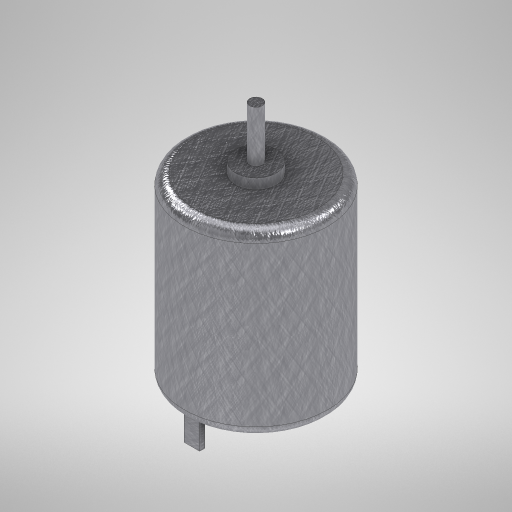
# Autodesk Inventor part: MOTOR
Saved by Autodesk Inventor 2023 (Build 270158000, 158)
## iProperties
Created: 2023-03-29
Part Number: MOTOR
Material: Genérico
Document SubType Name: Modeling
Designer: brand
Density: 1 g/cm^3
Appearance: Valor por defecto
Author: brand
Autodesk Inventor part; units mm, degrees
ref_plane "YZ Plane" through (0, 0, 0) normal (1, 0, 0) x (0, 1, 0)
ref_plane "XZ Plane" through (0, 0, 0) normal (0, 1, 0) x (-1, 0, 0)
ref_plane "XY Plane" through (0, 0, 0) normal (0, 0, 1) x (1, 0, 0)
sketch "Boceto1" plane through (0, 0, 0) normal (0, 1, 0) x (-1, 0, 0)
  circle A0 centre (0, 0) radius 14
  dimension "d0" = 28
  constraints: 1 centre point, 1 coincident
  measures "d0" diameter of A0
extrude "Extrusión1" add sketch "Boceto1" along normal blind 35
sketch "Boceto2" plane through (0, 0, 0) normal (0, -1, 0) x (1, 0, 0)
  line L0 (1.5, 12.5) -> (-1.5, 12.5)
  line L1 (-1.5, 12.5) -> (-1.5, 11.5)
  line L2 (-1.5, 11.5) -> (1.5, 11.5)
  line L3 (1.5, 11.5) -> (1.5, 12.5)
  line L4 (0, 0) -> (4.1398, 0)
  line L5 (1.5, -12.5) -> (-1.5, -12.5)
  line L6 (-1.5, -12.5) -> (-1.5, -11.5)
  line L7 (-1.5, -11.5) -> (1.5, -11.5)
  line L8 (1.5, -11.5) -> (1.5, -12.5)
  point P0 (-1.5, 12)
  point P1 (0, 11.5)
  point P2 (-1.5, -12)
  point P3 (0, -11.5)
  dimension "d3" = 12
  dimension "d4" = 3
  dimension "d5" = 1
  constraints: 18 end point, 6 symmetric about line, 3 perpendicular, 2 horizontal, 2 midpoint, 1 vertical alignment
  measures "d3" vertical distance of point (-1.5, 12) L4.start
  measures "d4" distance of L1.end L2.end
  measures "d5" distance of L2.end L0.start
extrude "Extrusión2" add sketch "Boceto2" along normal blind 5
sketch "Boceto3" plane through (0, 35, 0) normal (0, 1, 0) x (1, 0, 0)
  circle A0 centre (0, 0) radius 1.25
  dimension "d8" = 2.5
  constraints: 1 centre point, 1 coincident
  measures "d8" diameter of A0
extrude "Extrusión3" add sketch "Boceto3" along normal blind 12
fillet "Empalme1" radius 2 1 edges at (14, 35, 0)
sketch "Boceto4" plane through (0, 35, 0) normal (0, 1, 0) x (1, 0, 0)
  circle A0 centre (0, 0) radius 1.25 projected
  circle A1 centre (0, 0) radius 4
  dimension "d12" = 8
  constraints: 1 centre point, 1 coincident
  measures "d12" diameter of A1
extrude "Extrusión4" add sketch "Boceto4" along normal blind 2 contours A0 | A1
fillet "Empalme2" radius 2 1 edges at (14, 0, 0)
